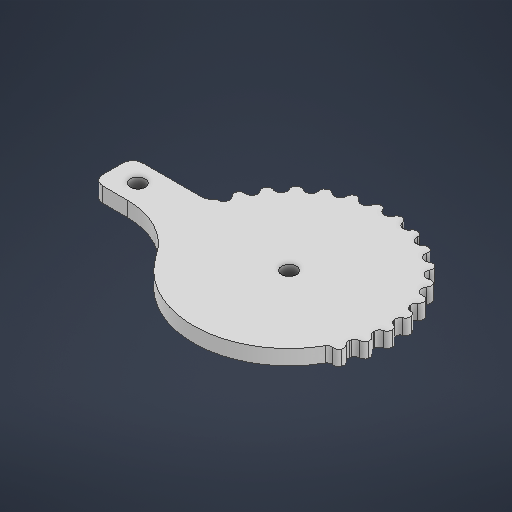
# Autodesk Inventor part: GarraBraçoP2
Saved by Autodesk Inventor 2027 (Build 310192060, 192F)
## iProperties
Created: 2026-10-09
Part Number: GarraBraçoP2
Material: Generic
Document SubType Name: Modeling
Designer: jose2
Density: 1 g/cm^3
Appearance: Default
Author: jose2
Autodesk Inventor part; units mm, degrees
ref_plane "YZ Plane" through (0, 0, 0) normal (1, 0, 0) x (0, 1, 0)
ref_plane "XZ Plane" through (0, 0, 0) normal (0, 1, 0) x (-1, 0, 0)
ref_plane "XY Plane" through (0, 0, 0) normal (0, 0, 1) x (1, 0, 0)
sketch "Sketch1" plane through (0, 0, 0) normal (0, 1, 0) x (-1, 0, 0)
  circle A0 centre (0, 0) radius 20.68
  circle A1 centre (0, 0) radius 1.5
  circle A2 centre (0, 0) radius 7
  circle A3 centre (0, 7) radius 1.5
  circle A4 centre (-7, 0) radius 1.5
  circle A5 centre (0, -7) radius 1.5
  circle A6 centre (7, 0) radius 1.5
  circle A7 centre (0, 0) radius 19.18
  line L0 (20.68, 0) -> (18.68, 0)
  line L1 (18.68, 0) -> (18.68, -1)
  line L2 (18.68, -1) -> (20.68, -1)
  line L3 (20.68, -1) -> (20.68, 0)
  line L4 (20.68, 0) -> (18.68, 0)
  line L5 (18.68, 0) -> (18.68, 1)
  line L6 (18.68, 1) -> (20.68, 1)
  line L7 (20.68, 1) -> (20.68, 0)
  line L8 (18.2718, 3.8838) -> (18.4797, 2.9056)
  line L9 (18.2718, 3.8838) -> (18.0639, 4.8619)
  line L10 (18.4797, 2.9056) -> (20.436, 3.3215)
  line L11 (20.436, 3.3215) -> (20.2281, 4.2996)
  line L12 (20.2281, 4.2996) -> (18.2718, 3.8838)
  line L13 (20.2281, 4.2996) -> (18.2718, 3.8838)
  line L14 (20.0202, 5.2778) -> (20.2281, 4.2996)
  line L15 (18.0639, 4.8619) -> (20.0202, 5.2778)
  line L16 (17.065, 7.5978) -> (17.4718, 6.6843)
  line L17 (17.065, 7.5978) -> (16.6583, 8.5114)
  line L18 (17.4718, 6.6843) -> (19.2989, 7.4978)
  line L19 (19.2989, 7.4978) -> (18.8921, 8.4113)
  line L20 (18.8921, 8.4113) -> (17.065, 7.5978)
  line L21 (18.8921, 8.4113) -> (17.065, 7.5978)
  line L22 (18.4854, 9.3249) -> (18.8921, 8.4113)
  line L23 (16.6583, 8.5114) -> (18.4854, 9.3249)
  line L24 (15.1124, 10.9798) -> (15.7002, 10.1708)
  line L25 (15.1124, 10.9798) -> (14.5247, 11.7888)
  line L26 (15.7002, 10.1708) -> (17.3183, 11.3464)
  line L27 (17.3183, 11.3464) -> (16.7305, 12.1554)
  line L28 (16.7305, 12.1554) -> (15.1124, 10.9798)
  line L29 (16.7305, 12.1554) -> (15.1124, 10.9798)
  line L30 (16.1427, 12.9644) -> (16.7305, 12.1554)
  line L31 (14.5247, 11.7888) -> (16.1427, 12.9644)
  line L32 (12.4994, 13.8819) -> (13.2425, 13.2128)
  line L33 (12.4994, 13.8819) -> (11.7562, 14.5511)
  line L34 (13.2425, 13.2128) -> (14.5808, 14.6991)
  line L35 (14.5808, 14.6991) -> (13.8376, 15.3682)
  line L36 (13.8376, 15.3682) -> (12.4994, 13.8819)
  line L37 (13.8376, 15.3682) -> (12.4994, 13.8819)
  line L38 (13.0945, 16.0374) -> (13.8376, 15.3682)
  line L39 (11.7562, 14.5511) -> (13.0945, 16.0374)
  line L40 (9.34, 16.1774) -> (10.206, 15.6774)
  line L41 (9.34, 16.1774) -> (8.474, 16.6774)
  line L42 (10.206, 15.6774) -> (11.206, 17.4094)
  line L43 (11.206, 17.4094) -> (10.34, 17.9094)
  line L44 (10.34, 17.9094) -> (9.34, 16.1774)
  line L45 (10.34, 17.9094) -> (9.34, 16.1774)
  line L46 (9.474, 18.4094) -> (10.34, 17.9094)
  line L47 (8.474, 16.6774) -> (9.474, 18.4094)
  line L48 (5.7724, 17.7657) -> (6.7235, 17.4567)
  line L49 (5.7724, 17.7657) -> (4.8214, 18.0748)
  line L50 (6.7235, 17.4567) -> (7.3415, 19.3588)
  line L51 (7.3415, 19.3588) -> (6.3905, 19.6678)
  line L52 (6.3905, 19.6678) -> (5.7724, 17.7657)
  line L53 (6.3905, 19.6678) -> (5.7724, 17.7657)
  line L54 (5.4394, 19.9769) -> (6.3905, 19.6678)
  line L55 (4.8214, 18.0748) -> (5.4394, 19.9769)
  line L56 (1.9526, 18.5777) -> (2.9471, 18.4731)
  line L57 (1.9526, 18.5777) -> (0.9581, 18.6822)
  line L58 (2.9471, 18.4731) -> (3.1562, 20.4622)
  line L59 (3.1562, 20.4622) -> (2.1616, 20.5667)
  line L60 (2.1616, 20.5667) -> (1.9526, 18.5777)
  line L61 (2.1616, 20.5667) -> (1.9526, 18.5777)
  line L62 (1.1671, 20.6712) -> (2.1616, 20.5667)
  line L63 (0.9581, 18.6822) -> (1.1671, 20.6712)
  line L64 (-1.9526, 18.5777) -> (-0.9581, 18.6822)
  line L65 (-1.9526, 18.5777) -> (-2.9471, 18.4731)
  line L66 (-0.9581, 18.6822) -> (-1.1671, 20.6712)
  line L67 (-1.1671, 20.6712) -> (-2.1616, 20.5667)
  line L68 (-2.1616, 20.5667) -> (-1.9526, 18.5777)
  line L69 (-2.1616, 20.5667) -> (-1.9526, 18.5777)
  line L70 (-3.1562, 20.4622) -> (-2.1616, 20.5667)
  line L71 (-2.9471, 18.4731) -> (-3.1562, 20.4622)
  line L72 (-5.7724, 17.7657) -> (-4.8214, 18.0748)
  line L73 (-5.7724, 17.7657) -> (-6.7235, 17.4567)
  line L74 (-4.8214, 18.0748) -> (-5.4394, 19.9769)
  line L75 (-5.4394, 19.9769) -> (-6.3905, 19.6678)
  line L76 (-6.3905, 19.6678) -> (-5.7724, 17.7657)
  line L77 (-6.3905, 19.6678) -> (-5.7724, 17.7657)
  line L78 (-7.3415, 19.3588) -> (-6.3905, 19.6678)
  line L79 (-6.7235, 17.4567) -> (-7.3415, 19.3588)
  line L80 (-9.34, 16.1774) -> (-8.474, 16.6774)
  line L81 (-9.34, 16.1774) -> (-10.206, 15.6774)
  line L82 (-8.474, 16.6774) -> (-9.474, 18.4094)
  line L83 (-9.474, 18.4094) -> (-10.34, 17.9094)
  line L84 (-10.34, 17.9094) -> (-9.34, 16.1774)
  line L85 (-10.34, 17.9094) -> (-9.34, 16.1774)
  line L86 (-11.206, 17.4094) -> (-10.34, 17.9094)
  line L87 (-10.206, 15.6774) -> (-11.206, 17.4094)
  line L88 (-12.4994, 13.8819) -> (-11.7562, 14.5511)
  line L89 (-12.4994, 13.8819) -> (-13.2425, 13.2128)
  line L90 (-11.7562, 14.5511) -> (-13.0945, 16.0374)
  line L91 (-13.0945, 16.0374) -> (-13.8376, 15.3682)
  line L92 (-13.8376, 15.3682) -> (-12.4994, 13.8819)
  line L93 (-13.8376, 15.3682) -> (-12.4994, 13.8819)
  line L94 (-14.5808, 14.6991) -> (-13.8376, 15.3682)
  line L95 (-13.2425, 13.2128) -> (-14.5808, 14.6991)
  line L96 (-15.1124, 10.9798) -> (-14.5247, 11.7888)
  line L97 (-15.1124, 10.9798) -> (-15.7002, 10.1708)
  line L98 (-14.5247, 11.7888) -> (-16.1427, 12.9644)
  line L99 (-16.1427, 12.9644) -> (-16.7305, 12.1554)
  line L100 (-16.7305, 12.1554) -> (-15.1124, 10.9798)
  line L101 (-16.7305, 12.1554) -> (-15.1124, 10.9798)
  line L102 (-17.3183, 11.3464) -> (-16.7305, 12.1554)
  line L103 (-15.7002, 10.1708) -> (-17.3183, 11.3464)
  line L104 (-17.065, 7.5978) -> (-16.6583, 8.5114)
  line L105 (-17.065, 7.5978) -> (-17.4718, 6.6843)
  line L106 (-16.6583, 8.5114) -> (-18.4854, 9.3249)
  line L107 (-18.4854, 9.3249) -> (-18.8921, 8.4113)
  line L108 (-18.8921, 8.4113) -> (-17.065, 7.5978)
  line L109 (-18.8921, 8.4113) -> (-17.065, 7.5978)
  line L110 (-19.2989, 7.4978) -> (-18.8921, 8.4113)
  line L111 (-17.4718, 6.6843) -> (-19.2989, 7.4978)
  line L112 (-18.2718, 3.8838) -> (-18.0639, 4.8619)
  line L113 (-18.2718, 3.8838) -> (-18.4797, 2.9056)
  line L114 (-18.0639, 4.8619) -> (-20.0202, 5.2778)
  line L115 (-20.0202, 5.2778) -> (-20.2281, 4.2996)
  line L116 (-20.2281, 4.2996) -> (-18.2718, 3.8838)
  line L117 (-20.2281, 4.2996) -> (-18.2718, 3.8838)
  line L118 (-20.436, 3.3215) -> (-20.2281, 4.2996)
  line L119 (-18.4797, 2.9056) -> (-20.436, 3.3215)
  line L120 (-18.68, 0) -> (-18.68, 1)
  line L121 (-18.68, 0) -> (-18.68, -1)
  line L122 (-18.68, 1) -> (-20.68, 1)
  line L123 (-20.68, 1) -> (-20.68, 0)
  line L124 (-20.68, 0) -> (-18.68, 0)
  line L125 (-20.68, 0) -> (-18.68, 0)
  line L126 (-20.68, -1) -> (-20.68, 0)
  line L127 (-18.68, -1) -> (-20.68, -1)
  line L128 (-18.2718, -3.8838) -> (-18.4797, -2.9056)
  line L129 (-18.2718, -3.8838) -> (-18.0639, -4.8619)
  line L130 (-18.4797, -2.9056) -> (-20.436, -3.3215)
  line L131 (-20.436, -3.3215) -> (-20.2281, -4.2996)
  line L132 (-20.2281, -4.2996) -> (-18.2718, -3.8838)
  line L133 (-20.2281, -4.2996) -> (-18.2718, -3.8838)
  line L134 (-20.0202, -5.2778) -> (-20.2281, -4.2996)
  line L135 (-18.0639, -4.8619) -> (-20.0202, -5.2778)
  line L136 (-17.065, -7.5978) -> (-17.4718, -6.6843)
  line L137 (-17.065, -7.5978) -> (-16.6583, -8.5114)
  line L138 (-17.4718, -6.6843) -> (-19.2989, -7.4978)
  line L139 (-19.2989, -7.4978) -> (-18.8921, -8.4113)
  line L140 (-18.8921, -8.4113) -> (-17.065, -7.5978)
  line L141 (-18.8921, -8.4113) -> (-17.065, -7.5978)
  line L142 (-18.4854, -9.3249) -> (-18.8921, -8.4113)
  line L143 (-16.6583, -8.5114) -> (-18.4854, -9.3249)
  line L144 (-15.1124, -10.9798) -> (-15.7002, -10.1708)
  line L145 (-15.1124, -10.9798) -> (-14.5247, -11.7888)
  line L146 (-15.7002, -10.1708) -> (-17.3183, -11.3464)
  line L147 (-17.3183, -11.3464) -> (-16.7305, -12.1554)
  line L148 (-16.7305, -12.1554) -> (-15.1124, -10.9798)
  line L149 (-16.7305, -12.1554) -> (-15.1124, -10.9798)
  line L150 (-16.1427, -12.9644) -> (-16.7305, -12.1554)
  line L151 (-14.5247, -11.7888) -> (-16.1427, -12.9644)
  line L152 (-12.4994, -13.8819) -> (-13.2425, -13.2128)
  line L153 (-12.4994, -13.8819) -> (-11.7562, -14.5511)
  line L154 (-13.2425, -13.2128) -> (-14.5808, -14.6991)
  line L155 (-14.5808, -14.6991) -> (-13.8376, -15.3682)
  line L156 (-13.8376, -15.3682) -> (-12.4994, -13.8819)
  line L157 (-13.8376, -15.3682) -> (-12.4994, -13.8819)
  line L158 (-13.0945, -16.0374) -> (-13.8376, -15.3682)
  line L159 (-11.7562, -14.5511) -> (-13.0945, -16.0374)
  line L160 (-9.34, -16.1774) -> (-10.206, -15.6774)
  line L161 (-9.34, -16.1774) -> (-8.474, -16.6774)
  line L162 (-10.206, -15.6774) -> (-11.206, -17.4094)
  line L163 (-11.206, -17.4094) -> (-10.34, -17.9094)
  line L164 (-10.34, -17.9094) -> (-9.34, -16.1774)
  line L165 (-10.34, -17.9094) -> (-9.34, -16.1774)
  line L166 (-9.474, -18.4094) -> (-10.34, -17.9094)
  line L167 (-8.474, -16.6774) -> (-9.474, -18.4094)
  line L168 (-5.7724, -17.7657) -> (-6.7235, -17.4567)
  line L169 (-5.7724, -17.7657) -> (-4.8214, -18.0748)
  line L170 (-6.7235, -17.4567) -> (-7.3415, -19.3588)
  line L171 (-7.3415, -19.3588) -> (-6.3905, -19.6678)
  line L172 (-6.3905, -19.6678) -> (-5.7724, -17.7657)
  line L173 (-6.3905, -19.6678) -> (-5.7724, -17.7657)
  line L174 (-5.4394, -19.9769) -> (-6.3905, -19.6678)
  line L175 (-4.8214, -18.0748) -> (-5.4394, -19.9769)
  line L176 (-1.9526, -18.5777) -> (-2.9471, -18.4731)
  line L177 (-1.9526, -18.5777) -> (-0.9581, -18.6822)
  line L178 (-2.9471, -18.4731) -> (-3.1562, -20.4622)
  line L179 (-3.1562, -20.4622) -> (-2.1616, -20.5667)
  line L180 (-2.1616, -20.5667) -> (-1.9526, -18.5777)
  line L181 (-2.1616, -20.5667) -> (-1.9526, -18.5777)
  line L182 (-1.1671, -20.6712) -> (-2.1616, -20.5667)
  line L183 (-0.9581, -18.6822) -> (-1.1671, -20.6712)
  line L184 (1.9526, -18.5777) -> (0.9581, -18.6822)
  line L185 (1.9526, -18.5777) -> (2.9471, -18.4731)
  line L186 (0.9581, -18.6822) -> (1.1671, -20.6712)
  line L187 (1.1671, -20.6712) -> (2.1616, -20.5667)
  line L188 (2.1616, -20.5667) -> (1.9526, -18.5777)
  line L189 (2.1616, -20.5667) -> (1.9526, -18.5777)
  line L190 (3.1562, -20.4622) -> (2.1616, -20.5667)
  line L191 (2.9471, -18.4731) -> (3.1562, -20.4622)
  line L192 (5.7724, -17.7657) -> (4.8214, -18.0748)
  line L193 (5.7724, -17.7657) -> (6.7235, -17.4567)
  line L194 (4.8214, -18.0748) -> (5.4394, -19.9769)
  line L195 (5.4394, -19.9769) -> (6.3905, -19.6678)
  line L196 (6.3905, -19.6678) -> (5.7724, -17.7657)
  line L197 (6.3905, -19.6678) -> (5.7724, -17.7657)
  line L198 (7.3415, -19.3588) -> (6.3905, -19.6678)
  line L199 (6.7235, -17.4567) -> (7.3415, -19.3588)
  line L200 (9.34, -16.1774) -> (8.474, -16.6774)
  line L201 (9.34, -16.1774) -> (10.206, -15.6774)
  line L202 (8.474, -16.6774) -> (9.474, -18.4094)
  line L203 (9.474, -18.4094) -> (10.34, -17.9094)
  line L204 (10.34, -17.9094) -> (9.34, -16.1774)
  line L205 (10.34, -17.9094) -> (9.34, -16.1774)
  line L206 (11.206, -17.4094) -> (10.34, -17.9094)
  line L207 (10.206, -15.6774) -> (11.206, -17.4094)
  line L208 (12.4994, -13.8819) -> (11.7562, -14.5511)
  line L209 (12.4994, -13.8819) -> (13.2425, -13.2128)
  line L210 (11.7562, -14.5511) -> (13.0945, -16.0374)
  line L211 (13.0945, -16.0374) -> (13.8376, -15.3682)
  line L212 (13.8376, -15.3682) -> (12.4994, -13.8819)
  line L213 (13.8376, -15.3682) -> (12.4994, -13.8819)
  line L214 (14.5808, -14.6991) -> (13.8376, -15.3682)
  line L215 (13.2425, -13.2128) -> (14.5808, -14.6991)
  line L216 (15.1124, -10.9798) -> (14.5247, -11.7888)
  line L217 (15.1124, -10.9798) -> (15.7002, -10.1708)
  line L218 (14.5247, -11.7888) -> (16.1427, -12.9644)
  line L219 (16.1427, -12.9644) -> (16.7305, -12.1554)
  line L220 (16.7305, -12.1554) -> (15.1124, -10.9798)
  line L221 (16.7305, -12.1554) -> (15.1124, -10.9798)
  line L222 (17.3183, -11.3464) -> (16.7305, -12.1554)
  line L223 (15.7002, -10.1708) -> (17.3183, -11.3464)
  line L224 (17.065, -7.5978) -> (16.6583, -8.5114)
  line L225 (17.065, -7.5978) -> (17.4718, -6.6843)
  line L226 (16.6583, -8.5114) -> (18.4854, -9.3249)
  line L227 (18.4854, -9.3249) -> (18.8921, -8.4113)
  line L228 (18.8921, -8.4113) -> (17.065, -7.5978)
  line L229 (18.8921, -8.4113) -> (17.065, -7.5978)
  line L230 (19.2989, -7.4978) -> (18.8921, -8.4113)
  line L231 (17.4718, -6.6843) -> (19.2989, -7.4978)
  line L232 (18.2718, -3.8838) -> (18.0639, -4.8619)
  line L233 (18.2718, -3.8838) -> (18.4797, -2.9056)
  line L234 (18.0639, -4.8619) -> (20.0202, -5.2778)
  line L235 (20.0202, -5.2778) -> (20.2281, -4.2996)
  line L236 (20.2281, -4.2996) -> (18.2718, -3.8838)
  line L237 (20.2281, -4.2996) -> (18.2718, -3.8838)
  line L238 (20.436, -3.3215) -> (20.2281, -4.2996)
  line L239 (18.4797, -2.9056) -> (20.436, -3.3215)
  point P0 (-17.0912, -8.7041)
  point P1 (-17.9047, -6.8771)
  point P2 (-16.1231, -12.9502)
  point P3 (-14.9081, -12.0674)
  point P4 (-16.0836, -10.4494)
  point P5 (-17.2987, -11.3322)
  point P6 (-13.0783, -16.0194)
  point P7 (-12.0733, -14.9033)
  point P8 (-13.5596, -13.565)
  point P9 (-14.5646, -14.6811)
  point P10 (-9.4619, -18.3885)
  point P11 (-8.7109, -17.0878)
  point P12 (-10.443, -16.0878)
  point P13 (-11.1939, -17.3885)
  point P14 (-5.4319, -19.9539)
  point P15 (-4.9678, -18.5255)
  point P16 (-6.8699, -17.9074)
  point P17 (-7.3341, -19.3358)
  point P18 (-2.9967, -18.9445)
  point P19 (-3.1536, -20.4381)
  point P20 (-1.1646, -20.6472)
  point P21 (-1.0076, -19.1535)
  point P22 (3.1536, -20.4381)
  point P23 (2.9967, -18.9445)
  point P24 (1.0076, -19.1535)
  point P25 (1.1646, -20.6472)
  point P26 (7.3341, -19.3358)
  point P27 (6.8699, -17.9074)
  point P28 (4.9678, -18.5255)
  point P29 (5.4319, -19.9539)
  point P30 (11.1939, -17.3885)
  point P31 (10.443, -16.0878)
  point P32 (8.7109, -17.0878)
  point P33 (9.4619, -18.3885)
  point P34 (14.5646, -14.6811)
  point P35 (13.5596, -13.565)
  point P36 (12.0733, -14.9033)
  point P37 (13.0783, -16.0194)
  point P38 (17.2987, -11.3322)
  point P39 (16.0836, -10.4494)
  point P40 (14.9081, -12.0674)
  point P41 (16.1231, -12.9502)
  point P42 (19.2768, -7.4879)
  point P43 (17.9047, -6.8771)
  point P44 (17.0912, -8.7041)
  point P45 (18.4633, -9.315)
  point P46 (20.4123, -3.3164)
  point P47 (18.9433, -3.0042)
  point P48 (18.5274, -4.9605)
  point P49 (19.9965, -5.2727)
  point P50 (20.6558, 1)
  point P51 (19.1539, 1)
  point P52 (19.1539, -1)
  point P53 (20.6558, -1)
  point P54 (-17.9047, 6.8771)
  point P55 (-17.0912, 8.7041)
  point P56 (-20.4123, 3.3164)
  point P57 (-18.9433, 3.0042)
  point P58 (-18.5274, 4.9605)
  point P59 (-19.9965, 5.2727)
  point P60 (-20.6558, -1)
  point P61 (-19.1539, -1)
  point P62 (-19.1539, 1)
  point P63 (-20.6558, 1)
  point P64 (-19.9965, -5.2727)
  point P65 (-18.5274, -4.9605)
  point P66 (-18.9433, -3.0042)
  point P67 (-20.4123, -3.3164)
  dimension "d0" = 41.36
  dimension "d2" = 14
  dimension "d8" = 38.36
  dimension "d1" = 3
  dimension "d6" = 360
  dimension "d11" = 2
  dimension "d12" = 1
  dimension "d13" = 1
  dimension "d16" = 360
  constraints: 480 end point, 30 point on line, 5 centre point, 4 parallel, 3 coincident, 2 horizontal, 2 perpendicular, 1 vertical alignment, 467 other
  measures "d1" diameter of A1
  measures "d11" distance of L2.end L1.end
  measures "d12" distance of L1.end L0.end
  measures "d13" distance of L4.end L5.end
extrude "Extrusion1" add sketch "Sketch1" along normal blind 3 contours L0 A7 L6 A0 | A0 L2 A7 L0 | L0 L5 L6 A7 | A7 L2 L1 L0 | L6 L5 L1 L2 A7 L239 L233 L232 L234 L231 L225 L224 L226 L223 L217 L216 L218 L215 L209 L208 L210 L207 L201 L200 L202 L199 L193 L192 L194 L191 L185 L184 L186 L183 L177 L176 L178 L175 L169 L168 L170 L167 L161 L160 L162 L159 L153 L152 L154 L151 L145 L144 L146 L143 L137 L136 L138 L135 L129 L128 L130 L127 L121 L120 L122 L119 L113 L112 L114 L111 L105 L104 L106 L103 L97 L96 L98 L95 L89 L88 L90 L87 L81 L80 L82 L79 L73 L72 L74 L71 L65 L64 L66 L63 L57 L56 L58 L55 L49 L48 L50 L47 L41 L40 L42 L39 L33 L32 L34 L31 L25 L24 L26 L23 L17 L16 L18 L15 L9 L8 L10 | A0 L236 A7 L239 | L10 L8 L12 A7 | A0 L234 A7 L236 | A7 L236 L233 L239 | L12 L9 L15 A7 | A7 L234 L232 L236 | A0 L228 A7 L231 | L18 L16 L20 A7 | A0 L226 A7 L228 | A7 L228 L225 L231 | L20 L17 L23 A7 | A7 L226 L224 L228 | A0 L220 A7 L223 | L26 L24 L28 A7 | A0 L218 A7 L220 | A7 L220 L217 L223 | L28 L25 L31 A7 | A7 L218 L216 L220 | A0 L212 A7 L215 | L34 L32 L36 A7 | A0 L210 A7 L212 | A7 L212 L209 L215 | L36 L33 L39 A7 | A7 L210 L208 L212 | A0 L204 A7 L207 | L42 L40 L44 A7 | A0 L202 A7 L204 | A7 L204 L201 L207 | L44 L41 L47 A7 | A7 L202 L200 L204 | A0 L196 A7 L199 | L50 L48 L52 A7 | A0 L194 A7 L196 | A7 L196 L193 L199 | L52 L49 L55 A7 | A7 L194 L192 L196 | A0 L188 A7 L191 | L58 L56 L60 A7 | A0 L186 A7 L188 | A7 L188 L185 L191 | L60 L57 L63 A7 | A7 L186 L184 L188 | A0 L180 A7 L183 | L66 L64 L68 A7 | A0 L178 A7 L180 | A7 L180 L177 L183 | L68 L65 L71 A7 | A7 L178 L176 L180 | A0 L172 A7 L175 | L74 L72 L76 A7 | A0 L170 A7 L172 | A7 L172 L169 L175 | L76 L73 L79 A7 | A7 L170 L168 L172 | A0 L164 A7 L167 | L82 L80 L84 A7 | A0 L162 A7 L164 | A7 L164 L161 L167 | L84 L81 L87 A7 | A7 L162 L160 L164 | A0 L156 A7 L159 | L90 L88 L92 A7 | A0 L154 A7 L156 | A7 L156 L153 L159 | L92 L89 L95 A7 | A7 L154 L152 L156 | A0 L148 A7 L151 | L98 L96 L100 A7 | A0 L146 A7 L148 | A7 L148 L145 L151 | L100 L97 L103 A7 | A7 L146 L144 L148 | L106 A7 L108 A0 | A0 L107 L106 | L143 L142 A0 | A0 L140 A7 L143 | L108 A7 L111 A0 | A0 L111 L110 | L106 L104 L108 A7 | L139 L138 A0 | A0 L138 A7 L140 | A7 L140 L137 L143 | L108 L105 L111 A7 | A7 L138 L136 L140 | L114 A7 L116 A0 | A0 L132 A7 L135 | L116 A7 L119 A0 | L114 L112 L116 A7 | A0 L130 A7 L132 | A7 L132 L129 L135 | L116 L113 L119 A7 | A7 L130 L128 L132 | L122 A7 L124 A0 | A0 L124 A7 L127 | L122 L120 L124 A7 | A7 L124 L121 L127 | A2 A6 | A2 A6 | A6 A2 A5 A4 A3 | A3 A2 | A2 A3 | A5 A2 | A2 A5 | A4 A2 | A2 A4
fillet "Fillet1" radius 1 72 edges at (-19.1539, 1.5, 1) (-20.6558, 1.5, 1) (-20.6558, 1.5, -1) (-19.1539, 1.5, -1) (-18.9433, 1.5, -3.0042) (-20.4123, 1.5, -3.3164) (-19.9965, 1.5, -5.2727) (-18.5274, 1.5, -4.9605) (-17.9047, 1.5, -6.8771) (-19.2768, 1.5, -7.4879) (-18.4633, 1.5, -9.315) (-17.0912, 1.5, -8.7041) (-16.0836, 1.5, -10.4494) (-17.2987, 1.5, -11.3322) (-16.1231, 1.5, -12.9502) (-14.9081, 1.5, -12.0674) (-13.5596, 1.5, -13.565) (-14.5646, 1.5, -14.6811) (-13.0783, 1.5, -16.0194) (-12.0733, 1.5, -14.9033) (-10.443, 1.5, -16.0878) (-11.1939, 1.5, -17.3885) (-9.4619, 1.5, -18.3885) (-8.7109, 1.5, -17.0878) (-6.8699, 1.5, -17.9074) (-7.3341, 1.5, -19.3358) (-5.4319, 1.5, -19.9539) (-4.9678, 1.5, -18.5255) (-2.9967, 1.5, -18.9445) (-3.1536, 1.5, -20.4381) (-1.1646, 1.5, -20.6472) (-1.0076, 1.5, -19.1535) (1.0076, 1.5, -19.1535) (1.1646, 1.5, -20.6472) (3.1536, 1.5, -20.4381) (2.9967, 1.5, -18.9445) (4.9678, 1.5, -18.5255) (5.4319, 1.5, -19.9539) (7.3341, 1.5, -19.3358) (6.8699, 1.5, -17.9074) (8.7109, 1.5, -17.0878) (9.4619, 1.5, -18.3885) (11.1939, 1.5, -17.3885) (10.443, 1.5, -16.0878) (12.0733, 1.5, -14.9033) (13.0783, 1.5, -16.0194) (14.5646, 1.5, -14.6811) (13.5596, 1.5, -13.565) (14.9081, 1.5, -12.0674) (16.1231, 1.5, -12.9502) (17.2987, 1.5, -11.3322) (16.0836, 1.5, -10.4494) (17.0912, 1.5, -8.7041) (18.4854, 1.5, -9.3249) (19.2989, 1.5, -7.4978) (17.9047, 1.5, -6.8771) (18.5274, 1.5, -4.9605) (19.9965, 1.5, -5.2727) (20.4123, 1.5, -3.3164) (18.9433, 1.5, -3.0042) (19.1539, 1.5, -1) (20.6558, 1.5, -1) (20.6558, 1.5, 1) (19.1539, 1.5, 1) (18.9433, 1.5, 3.0042) (20.4123, 1.5, 3.3164) (19.9965, 1.5, 5.2727) (18.5274, 1.5, 4.9605) (17.9047, 1.5, 6.8771) (19.2989, 1.5, 7.4978) (18.4854, 1.5, 9.3249) (17.0912, 1.5, 8.7041)
sketch "Sketch2" plane through (0, 3, 0) normal (0, 1, 0) x (1, 0, 0)
  line L0 (-15.3195, 0) -> (-15.3195, -4)
  line L1 (-15.3195, -4) -> (-35.3195, -4)
  line L2 (-35.3195, -4) -> (-35.3195, 0)
  line L3 (-35.3195, 0) -> (-15.3195, 0)
  line L4 (-15.3195, 0) -> (-15.3195, 4)
  line L5 (-15.3195, 4) -> (-35.3195, 4)
  line L6 (-35.3195, 4) -> (-35.3195, 0)
  line L7 (-35.3195, 0) -> (-15.3195, 0)
  circle A0 centre (0, 0) radius 1.5 projected
  circle A1 centre (0, 0) radius 19.18
  circle A2 centre (-28.4125, -19) radius 15
  arc A3 (-19.0856, -1.9009) -> (16.6819, -9.465) centre (0, 0) ccw projected
  point P0 (-35.3195, 0)
  point P1 (-28.4125, -4)
  point P2 (-15.9436, -10.6618)
  point P3 (-18.7583, -4)
  dimension "d21" = 4
  dimension "d22" = 20
  dimension "d23" = 4
  dimension "d26" = 30
  dimension "d32" = 35.3195
  dimension "d33" = 15.3195
  constraints: 16 end point, 4 parallel, 2 centre point, 2 perpendicular, 2 tangent, 1 coincident, 1 point on line, 1 vertical
  measures "d21" distance of L0.start L0.end
  measures "d22" distance of L0.end L1.end
  measures "d23" distance of L0.start L4.end
  measures "d26" diameter of A2
  measures "d32" distance from line of L6 point (0, 0)
  measures "d33" distance from line of L4 point (0, 0)
extrude "Extrusion3" add sketch "Sketch2" against normal blind 3 contours L0 L1 A1 L3 | L3 A1 L5 L4 | A1 L1 L2 L3 | L3 L6 L5 A1 | A1 A2 L1
fillet "Fillet2" radius 2 3 edges at (-35.3195, 1.5, 4) (-35.3195, 1.5, -4) (-20.257, 1.5, -4)
sketch "Sketch3" plane through (0, 3, 0) normal (0, 1, 0) x (1, 0, 0)
  circle A0 centre (-30.3195, 0) radius 1.5
  line L0 (-35.3195, 2) -> (-35.3195, -2) projected
  point P0 (0, 0)
  point P1 (-35.3195, 0)
  dimension "d28" = 3
  dimension "d29" = 5
  constraints: 1 centre point, 1 midpoint
  measures "d28" diameter of A0
  measures "d29" distance of A0.centre point (-35.319, 0)
extrude "Extrusion4" cut sketch "Sketch3" against normal blind 3
body "Solid1"
